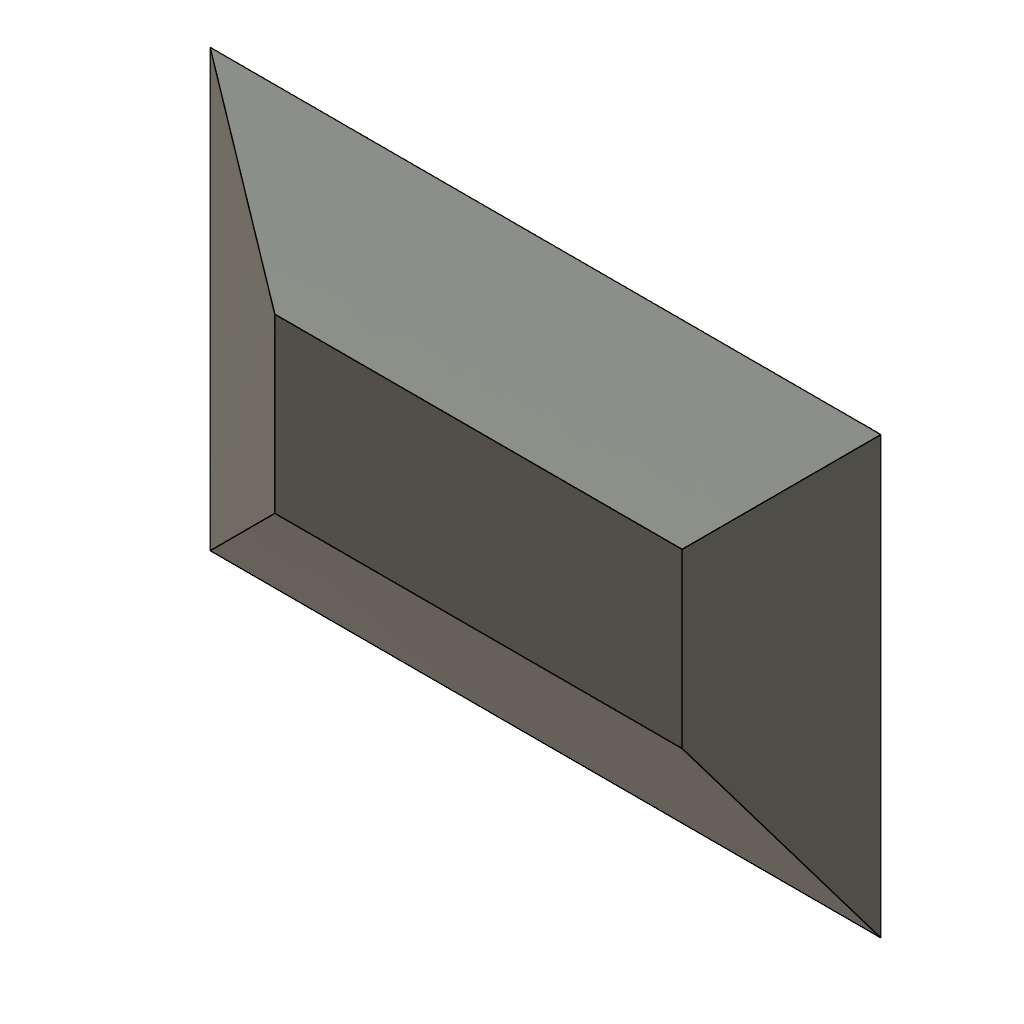
DraftSteep (Autodesk Fusion 360 design; units mm, degrees)
part number: 2026-11-14-20-01-35-576
Autodesk Fusion 360 part; units mm, degrees
sketch "RectangleSketch" plane through (0, 0, 0) normal (0, 0, 1) x (1, 0, 0)
  line L0 (0, 0) -> (20, 0)
  line L1 (20, 0) -> (20, 13)
  line L2 (20, 13) -> (0, 13)
  line L3 (0, 13) -> (0, 0)
  dimension "width_mm" = 20
  dimension "height_mm" = 13
  constraint horizontal L0
  constraint vertical L1
  constraint horizontal L2
  constraint vertical L3
  constraint coincident L0.start L3.end
  measures "width_mm" horizontal distance of L0.start L0.end
  measures "height_mm" vertical distance of L0.start L2.end
extrude "BlindBoss" add sketch "RectangleSketch" along normal blind 2 draft -63.025
equation "depth_mm = 2 mm"
